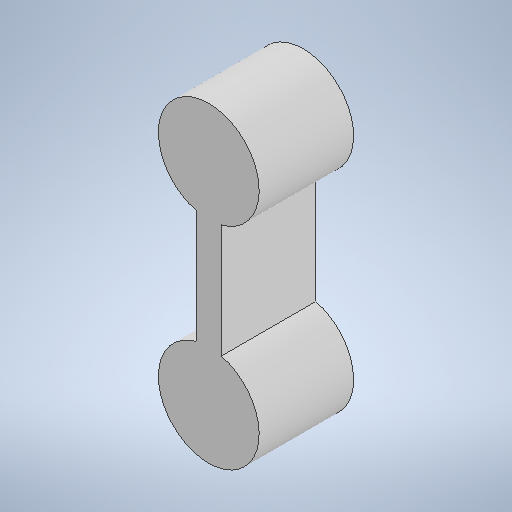
# Autodesk Inventor part: hub
Saved by Autodesk Inventor 2025.3 (Build 293356030, 356C)
## iProperties
Created: 2026-04-01
Part Number: hub
Material: 一般
Document SubType Name: Modeling
Designer: ibuki_ono
Density: 1 g/cm^3
Appearance: 既定
Author: ibuki_ono
## iProperties of the stored document hub_3D プリント.ipt
Created: 2026-04-01
Part Number: hub_3D プリント
Material: 一般
Document SubType Name: Modeling
Designer: ibuki_ono
Density: 1 g/cm^3
Appearance: 既定
Author: ibuki_ono
Autodesk Inventor part; units mm, degrees
ref_plane "YZ Plane" through (0, 0, 0) normal (1, 0, 0) x (0, 1, 0)
ref_plane "XZ Plane" through (0, 0, 0) normal (0, 1, 0) x (-1, 0, 0)
ref_plane "XY Plane" through (0, 0, 0) normal (0, 0, 1) x (1, 0, 0)
sketch "スケッチ1" plane through (0, 0, 0) normal (0, 0, 1) x (1, 0, 0)
  circle A0 centre (0, 0) radius 24.75
  circle A1 centre (0, 0) radius 19.75
  line L0 (0, 0) -> (4.2978, 24.374)
  line L1 (0, 0) -> (24.75, 0) construction
  line L2 (0, 0) -> (-4.2978, 24.374)
  line L3 (0, 0) -> (24.75, 0) construction
  line L4 (-2, -11.3426) -> (2, -11.3426)
  line L5 (2, -11.3426) -> (2, 11.3426)
  line L6 (2, 11.3426) -> (-2, 11.3426)
  line L7 (-2, 11.3426) -> (-2, -11.3426)
  line L8 (-2, -11.3426) -> (2, 11.3426) construction
  line L9 (2, -11.3426) -> (-2, 11.3426) construction
  line L10 (-2, 0) -> (2, 0)
  circle A2 centre (0, 16.75) radius 8
  point P0 (0, 0)
  point P1 (-1.5703, 8.9056)
  point P2 (1.5703, 8.9056)
  point P3 (-2, 9.004)
  point P4 (4.1585, 23.5842)
  point P5 (2, 9.004)
  point P6 (-4.1585, 23.5842)
  dimension "d0" = 49.5
  dimension "d1" = 5
  dimension "d2" = 80
  dimension "d3" = 100
  dimension "d4" = 4
  dimension "d7" = 16
  constraints: 22 end point, 5 midpoint, 3 centre point, 3 horizontal, 2 equal length, 2 parallel, 2 point on circle, 1 coincident, 1 perpendicular, 1 point on line, 1 tangent, 1 vertical alignment
  measures "d0" diameter of A0
  measures "d1" radial gap between concentric circles of A0 A1
  measures "d2" angle of L1 L0
  measures "d3" angle of L3 L2
  measures "d4" distance of L5.end L6.end
  measures "d7" diameter of A2
extrude "押し出し1" add sketch "スケッチ1" along normal mid plane 15 contours A2 L0 A1 L2 | A2 A1 L0 | L2 A1 A2 | L0 L6 L2 A1 | A1 A2 L5 L0 | L2 L7 A2 A1 | L5 A2 L0 | L0 A2 L2 L6 | L2 A2 L7 | A2 L2 L10 L7 | A2 L5 L10 L0 | L0 L2 A2 | L10 L5 L4 L7
mirror "ミラー1" about plane through (0, 0, 0) normal (0, 1, 0) of "押し出し1"
